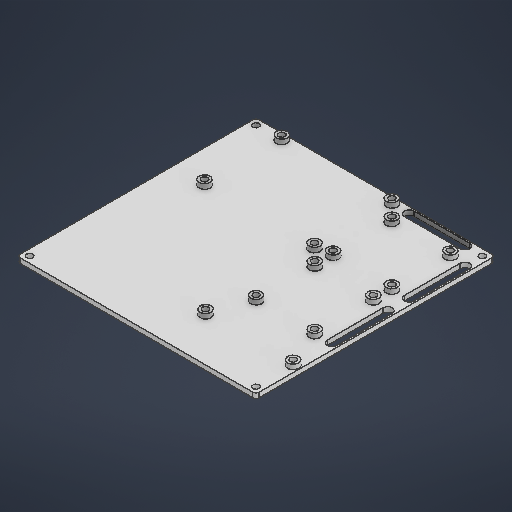
# Autodesk Inventor part: Power board
Saved by Autodesk Inventor 2026.2 (Build 302298010, 298A)
## iProperties
Created: 2026-04-28
Part Number: Power board
Material: 일반
Document SubType Name: Modeling
Designer: work
Density: 1 g/cm^3
Appearance: 기본값
Author: work
Autodesk Inventor part; units mm, degrees
ref_plane "YZ Plane" through (0, 0, 0) normal (1, 0, 0) x (0, 1, 0)
ref_plane "XZ Plane" through (0, 0, 0) normal (0, 1, 0) x (-1, 0, 0)
ref_plane "XY Plane" through (0, 0, 0) normal (0, 0, 1) x (1, 0, 0)
sketch "스케치1" plane through (0, 0, 0) normal (0, 1, 0) x (-1, 0, 0)
  line L0 (0, -150) -> (150, -150)
  line L1 (150, -150) -> (150, 0)
  line L2 (150, 0) -> (0, 0)
  line L3 (0, 0) -> (0, -150)
  line L4 (0, -150) -> (150, 0) construction
  line L5 (150, -150) -> (0, 0) construction
  line L6 (4, -4) -> (146, -4) construction
  line L7 (146, -4) -> (146, -146) construction
  line L8 (146, -146) -> (4, -146) construction
  line L9 (4, -146) -> (4, -4) construction
  line L10 (4, -4) -> (146, -146) construction
  line L11 (146, -4) -> (4, -146) construction
  line L12 (14, -99.2) -> (50.8, -99.2) construction
  line L13 (50.8, -99.2) -> (50.8, -136) construction
  line L14 (50.8, -136) -> (14, -136) construction
  line L15 (14, -136) -> (14, -99.2) construction
  line L16 (14, -99.2) -> (50.8, -136) construction
  line L17 (50.8, -99.2) -> (14, -136) construction
  circle A0 centre (14, -99.2) radius 2
  circle A1 centre (14, -136) radius 2
  circle A2 centre (50.8, -136) radius 2
  circle A3 centre (50.8, -99.2) radius 2
  line L18 (14.9, -146) -> (49.9, -146) construction
  line L19 (14.9, -149) -> (49.9, -149)
  line L20 (49.9, -143) -> (14.9, -143)
  arc A4 (14.9, -143) -> (14.9, -149) centre (14.9, -146) ccw
  arc A5 (49.9, -149) -> (49.9, -143) centre (49.9, -146) ccw
  line L21 (32.4, -117.6) -> (32.4, -146) construction
  line L22 (50.8, -50.8321) -> (50.8, -87.6321) construction
  line L23 (14, -50.8321) -> (50.8, -50.8321) construction
  line L24 (50.8, -50.8321) -> (14, -87.6321) construction
  line L25 (50.8, -87.6321) -> (14, -50.8321) construction
  line L26 (14, -87.6321) -> (14, -50.8321) construction
  line L27 (50.8, -87.6321) -> (14, -87.6321) construction
  circle A6 centre (50.8, -50.8321) radius 2
  circle A7 centre (14, -50.8321) radius 2
  circle A8 centre (14, -87.6321) radius 2
  circle A9 centre (50.8, -87.6321) radius 2
  arc A10 (7, -51.7321) -> (1, -51.7321) centre (4, -51.7321) ccw
  line L28 (32.4, -69.2321) -> (4, -69.2321) construction
  line L29 (4, -86.7321) -> (4, -51.7321) construction
  line L30 (7, -86.7321) -> (7, -51.7321)
  arc A11 (1, -86.7321) -> (7, -86.7321) centre (4, -86.7321) ccw
  line L31 (1, -51.7321) -> (1, -86.7321)
  line L32 (60.8, -97.5) -> (129.8, -97.5) construction
  line L33 (129.8, -97.5) -> (129.8, -146) construction
  line L34 (129.8, -146) -> (60.8, -146) construction
  line L35 (60.8, -146) -> (60.8, -97.5) construction
  line L36 (60.8, -97.5) -> (129.8, -146) construction
  line L37 (129.8, -97.5) -> (60.8, -146) construction
  circle A12 centre (60.8, -97.5) radius 2
  circle A13 centre (60.8, -146) radius 2
  circle A14 centre (129.8, -146) radius 2
  circle A15 centre (129.8, -97.5) radius 2
  line L38 (59, -27.3321) -> (4, -27.3321) construction
  line L39 (8.5, -13.8321) -> (54.5, -13.8321) construction
  line L40 (54.5, -13.8321) -> (54.5, -40.8321) construction
  line L41 (54.5, -40.8321) -> (8.5, -40.8321) construction
  line L42 (8.5, -40.8321) -> (8.5, -13.8321) construction
  line L43 (8.5, -13.8321) -> (54.5, -40.8321) construction
  line L44 (54.5, -13.8321) -> (8.5, -40.8321) construction
  circle A16 centre (59, -27.3321) radius 2
  circle A17 centre (4, -27.3321) radius 2
  circle A18 centre (4, -4) radius 2
  circle A19 centre (4, -146) radius 2
  circle A20 centre (146, -146) radius 2
  circle A21 centre (146, -4) radius 2
  line L45 (4, -135.1) -> (4, -100.1) construction
  line L46 (7, -135.1) -> (7, -100.1)
  line L47 (1, -100.1) -> (1, -135.1)
  arc A22 (1, -135.1) -> (7, -135.1) centre (4, -135.1) ccw
  arc A23 (7, -100.1) -> (1, -100.1) centre (4, -100.1) ccw
  point P0 (75, -75)
  point P1 (32.4, -87.6321)
  point P2 (95.3, -121.75)
  point P3 (31.5, -27.3321)
  point P4 (4, -117.6)
  dimension "d0" = 150
  dimension "d1" = 150
  dimension "d2" = 4
  dimension "d3" = 36.8
  dimension "d4" = 36.8
  dimension "d5" = 4
  dimension "d6" = 4
  dimension "d7" = 4
  dimension "d8" = 4
  dimension "d9" = 6
  dimension "d10" = 35
  dimension "d11" = 10
  dimension "d12" = 10
  dimension "d13" = 36.8
  dimension "d14" = 36.8
  dimension "d15" = 4
  dimension "d16" = 4
  dimension "d17" = 4
  dimension "d18" = 4
  dimension "d19" = 6
  dimension "d20" = 35
  dimension "d21" = 28.4
  dimension "d22" = 69
  dimension "d23" = 48.5
  dimension "d24" = 4
  dimension "d25" = 4
  dimension "d26" = 4
  dimension "d27" = 4
  dimension "d28" = 10
  dimension "d29" = 11.5679
  dimension "d30" = 55
  dimension "d31" = 46
  dimension "d32" = 27
  dimension "d33" = 4
  dimension "d34" = 4
  dimension "d35" = 10
  dimension "d36" = 4
  dimension "d37" = 4
  dimension "d38" = 4
  dimension "d39" = 4
  dimension "d40" = 17.5
  dimension "d41" = 6
  constraints: 102 end point, 24 centre point, 19 coincident, 17 midpoint, 15 parallel, 12 point on circle, 12 tangent, 8 horizontal, 7 point on line, 6 perpendicular, 2 vertical
  measures "d0" distance of L2.end L1.end
  measures "d1" distance of L1.end L0.end
  measures "d2" distance between parallel lines of L1 L7
  measures "d3" distance of L13.end L14.end
  measures "d4" distance of L13.start L13.end
  measures "d5" diameter of A0
  measures "d6" diameter of A1
  measures "d7" diameter of A2
  measures "d8" diameter of A3
  measures "d9" diameter of A5
  measures "d10" distance of L18.start L18.end
  measures "d11" horizontal distance of L8.end A1.centre
  measures "d12" horizontal distance of L8.end L14.end
  measures "d13" distance of L26.start L26.end
  measures "d14" distance of L27.start L26.start
  measures "d15" diameter of A6
  measures "d16" diameter of A7
  measures "d17" diameter of A8
  measures "d18" diameter of A9
  measures "d19" diameter of A10
  measures "d20" distance of L29.start L29.end
  measures "d21" distance of L28.start L28.end
  measures "d22" distance of L34.start L35.start
  measures "d23" distance of L32.end L34.start
  measures "d24" diameter of A12
  measures "d25" diameter of A13
  measures "d26" diameter of A14
  measures "d27" diameter of A15
  measures "d28" distance between parallel lines of L13 L35
  measures "d29" distance between parallel lines of L12 L27
  measures "d30" distance of L38.start L38.end
  measures "d31" distance of L40.end L44.end
  measures "d32" distance of L39.end L40.end
  measures "d33" diameter of A16
  measures "d34" diameter of A17
  measures "d35" distance between parallel lines of L23 L41
  measures "d36" diameter of A18
  measures "d37" diameter of A19
  measures "d38" diameter of A20
  measures "d39" diameter of A21
  measures "d40" distance of point (4, -117.6) L45.end
  measures "d41" diameter of A23
extrude "돌출1" add sketch "스케치1" along normal blind 3
sketch "스케치2" plane through (0, 3, 0) normal (0, 1, 0) x (1, 0, 0)
  line L0 (-7, 100.1) -> (-7, 135.1) projected
  line L1 (-150, 150) -> (-150, 0) projected
  line L2 (-150, 0) -> (0, 0) projected
  line L3 (0, 0) -> (0, 150) projected
  line L4 (0, 150) -> (-150, 150) projected
  circle A0 centre (-146, 4) radius 2 projected
  circle A1 centre (-4, 146) radius 2 projected
  circle A2 centre (-4, 27.3321) radius 2 projected
  circle A3 centre (-129.8, 146) radius 2 projected
  circle A4 centre (-129.8, 97.5) radius 2 projected
  circle A5 centre (-50.8, 87.6321) radius 2 projected
  circle A6 centre (-50.8, 50.8321) radius 2 projected
  circle A7 centre (-14, 87.6321) radius 2 projected
  circle A8 centre (-14, 50.8321) radius 2 projected
  circle A9 centre (-50.8, 136) radius 2 projected
  circle A10 centre (-14, 136) radius 2 projected
  circle A11 centre (-14, 99.2) radius 2 projected
  circle A12 centre (-50.8, 99.2) radius 2 projected
  circle A13 centre (-60.8, 97.5) radius 2 projected
  circle A14 centre (-60.8, 146) radius 2 projected
  circle A15 centre (-59, 27.3321) radius 2 projected
  circle A16 centre (-4, 4) radius 2 projected
  circle A17 centre (-146, 146) radius 2 projected
  arc A18 (-1, 135.1) -> (-7, 135.1) centre (-4, 135.1) ccw projected
  line L5 (-1, 135.1) -> (-1, 100.1) projected
  arc A19 (-7, 100.1) -> (-1, 100.1) centre (-4, 100.1) ccw projected
  line L6 (-7, 100.1) -> (-7, 135.1) projected
  line L7 (-7, 51.7321) -> (-7, 86.7321) projected
  arc A20 (-1, 86.7321) -> (-7, 86.7321) centre (-4, 86.7321) ccw projected
  line L8 (-1, 86.7321) -> (-1, 51.7321) projected
  arc A21 (-7, 51.7321) -> (-1, 51.7321) centre (-4, 51.7321) ccw projected
  line L9 (-49.9, 149) -> (-14.9, 149) projected
  arc A22 (-14.9, 143) -> (-14.9, 149) centre (-14.9, 146) ccw projected
  line L10 (-14.9, 143) -> (-49.9, 143) projected
  arc A23 (-49.9, 149) -> (-49.9, 143) centre (-49.9, 146) ccw projected
  circle A24 centre (-14, 87.6321) radius 2 projected
  circle A25 centre (-14, 50.8321) radius 2 projected
  circle A26 centre (-129.8, 146) radius 2 projected
  circle A27 centre (-4, 27.3321) radius 3.5
  dimension "d44" = 7
  constraints: 15 coincident, 1 centre point
  measures "d44" diameter of A27
extrude "돌출2" add sketch "스케치2" along normal blind 3 contours A27
pattern_sketch "스케치 연계 패턴1" of "돌출2" from (-4, 3, -27.3321) copies at (-14, 3, -136) at (-50.8, 3, -136) at (-60.8, 3, -146) at (-60.8, 3, -97.5) at (-50.8, 3, -99.2) at (-50.8, 3, -87.6321) at (-14, 3, -99.2) at (-14, 3, -87.6321) at (-14, 3, -50.8321) at (-59, 3, -27.3321) at (-50.8, 3, -50.8321) at (-129.8, 3, -97.5) at (-129.8, 3, -146)
fillet "모깎기1" radius 2 4 edges at (-150, 1.5, 0) (0, 1.5, 0) (0, 1.5, -150) (-150, 1.5, -150)
